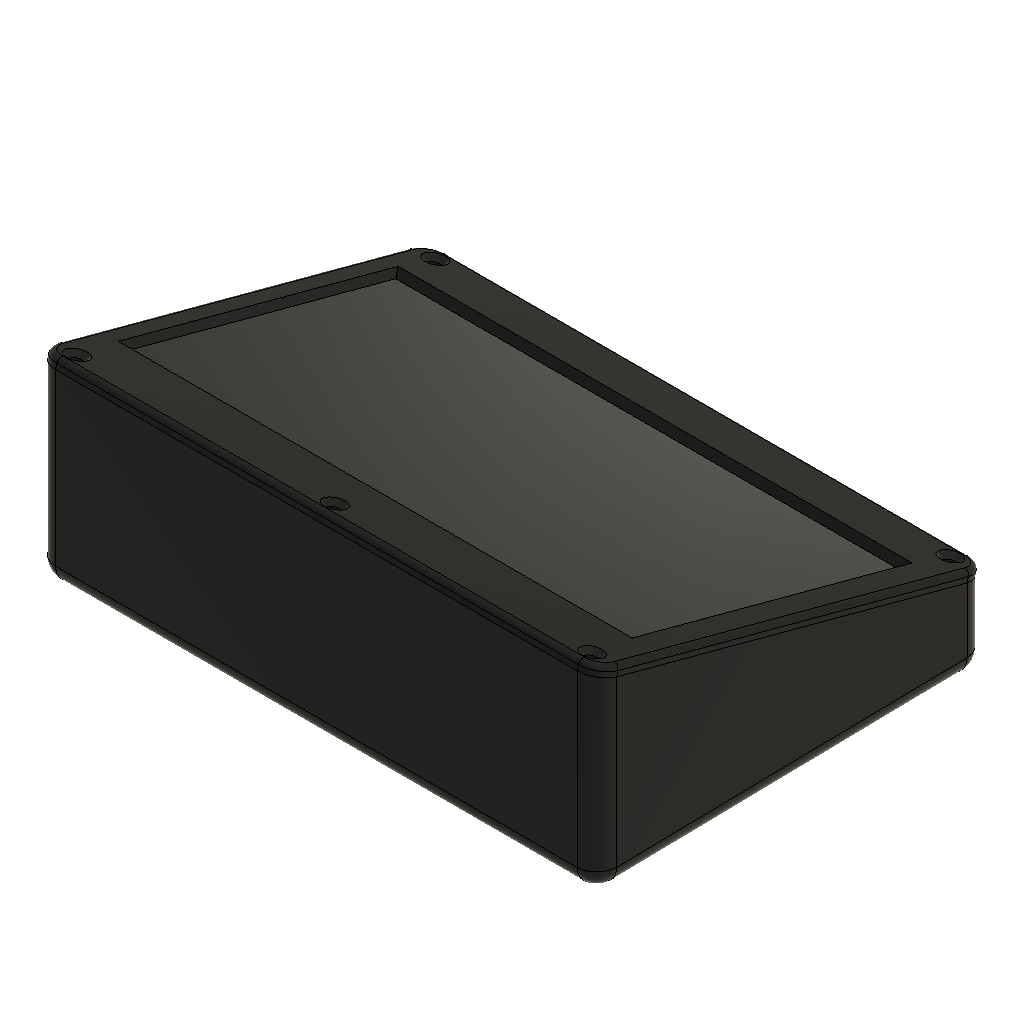
RadioCaseShort (Autodesk Fusion 360 design; units mm, degrees)
part number: 2026-10-21-15-02-30-773
Autodesk Fusion 360 part; units mm, degrees
sketch "Sketch1" plane through (0, 0, 0) normal (1, 0, 0) x (0, 0, -1)
  line L0 (0, 0) -> (0, 123)
  line L1 (0, 123) -> (23.1822, 129.2117)
  line L2 (23.1822, 129.2117) -> (56.0237, 15.0115)
  line L3 (56.0237, 15.0115) -> (0, 0)
extrude "Extrude1" add sketch "Sketch1" along normal blind 171 makes body 1
fillet "Fillet1" radius 6 8 edges at (0, 7.5058, -28.0118) (85.5, 15.0115, -56.0237) (171, 7.5058, -28.0118) (0, 126.1058, -11.5911) (171, 126.1058, -11.5911) (85.5, 129.2117, -23.1822) (0, 72.1116, -39.603) (171, 72.1116, -39.603) on bodies 1
extrude "Extrude2" add 1 faces at (59, 41, 0) along direction (0, 0, 1) blind 3 separate body on bodies 1 makes body 2
ref_plane "WorkPlane1" through (0, 0, -61.0237) normal (0, 0, 1) x (1, 0, 0)
sketch "Sketch2" plane through (0, 0, -61.0237) normal (0, 0, 1) x (1, 0, 0)
  circle A0 centre (40.5, 36) radius 4.5
extrude "Extrude3" add sketch "Sketch2" along normal blind 44.7237 separate body makes body 3
ref_plane "WorkPlane2" through (0, 0, -16.3) normal (0, 0, 1) x (1, 0, 0)
sketch "Sketch3" plane through (0, 0, -16.3) normal (0, 0, 1) x (1, 0, 0)
  circle A0 centre (40.5, 36) radius 3.5
extrude "Extrude4" add sketch "Sketch3" along normal blind 6 bodies 3
ref_plane "WorkPlane3" through (0, 0, -61.0237) normal (0, 0, 1) x (1, 0, 0)
sketch "Sketch4" plane through (0, 0, -61.0237) normal (0, 0, 1) x (1, 0, 0)
  circle A0 centre (40.5, 88) radius 4.5
extrude "Extrude5" add sketch "Sketch4" along normal blind 44.7237 separate body makes body 4
ref_plane "WorkPlane4" through (0, 0, -16.3) normal (0, 0, 1) x (1, 0, 0)
sketch "Sketch5" plane through (0, 0, -16.3) normal (0, 0, 1) x (1, 0, 0)
  circle A0 centre (40.5, 88) radius 3.5
extrude "Extrude6" add sketch "Sketch5" along normal blind 6 bodies 4
ref_plane "WorkPlane5" through (0, 0, -61.0237) normal (0, 0, 1) x (1, 0, 0)
sketch "Sketch6" plane through (0, 0, -61.0237) normal (0, 0, 1) x (1, 0, 0)
  circle A0 centre (130.5, 36) radius 4.5
extrude "Extrude7" add sketch "Sketch6" along normal blind 44.7237 separate body makes body 5
ref_plane "WorkPlane6" through (0, 0, -16.3) normal (0, 0, 1) x (1, 0, 0)
sketch "Sketch7" plane through (0, 0, -16.3) normal (0, 0, 1) x (1, 0, 0)
  circle A0 centre (130.5, 36) radius 3.5
extrude "Extrude8" add sketch "Sketch7" along normal blind 6 bodies 5
ref_plane "WorkPlane7" through (0, 0, -61.0237) normal (0, 0, 1) x (1, 0, 0)
sketch "Sketch8" plane through (0, 0, -61.0237) normal (0, 0, 1) x (1, 0, 0)
  circle A0 centre (130.5, 88) radius 4.5
extrude "Extrude9" add sketch "Sketch8" along normal blind 44.7237 separate body makes body 6
ref_plane "WorkPlane8" through (0, 0, -16.3) normal (0, 0, 1) x (1, 0, 0)
sketch "Sketch9" plane through (0, 0, -16.3) normal (0, 0, 1) x (1, 0, 0)
  circle A0 centre (130.5, 88) radius 3.5
extrude "Extrude10" add sketch "Sketch9" along normal blind 6 bodies 6
ref_plane "WorkPlane9" through (0, 0, -61.0237) normal (0, 0, 1) x (1, 0, 0)
sketch "Sketch10" plane through (0, 0, -61.0237) normal (0, 0, 1) x (1, 0, 0)
  circle A0 centre (7, 5) radius 3.5
extrude "Extrude11" add sketch "Sketch10" along normal blind 61.0237 separate body makes body 7
ref_plane "WorkPlane10" through (0, 0, -61.0237) normal (0, 0, 1) x (1, 0, 0)
sketch "Sketch11" plane through (0, 0, -61.0237) normal (0, 0, 1) x (1, 0, 0)
  circle A0 centre (85.5, 5) radius 3.5
extrude "Extrude12" add sketch "Sketch11" along normal blind 61.0237 separate body makes body 8
ref_plane "WorkPlane11" through (0, 0, -61.0237) normal (0, 0, 1) x (1, 0, 0)
sketch "Sketch12" plane through (0, 0, -61.0237) normal (0, 0, 1) x (1, 0, 0)
  circle A0 centre (164, 5) radius 3.5
extrude "Extrude13" add sketch "Sketch12" along normal blind 61.0237 separate body makes body 9
ref_plane "WorkPlane12" through (0, 0, -61.0237) normal (0, 0, 1) x (1, 0, 0)
sketch "Sketch13" plane through (0, 0, -61.0237) normal (0, 0, 1) x (1, 0, 0)
  circle A0 centre (7, 118) radius 3.5
extrude "Extrude14" add sketch "Sketch13" along normal blind 61.0237 separate body makes body 10
ref_plane "WorkPlane13" through (0, 0, -61.0237) normal (0, 0, 1) x (1, 0, 0)
sketch "Sketch14" plane through (0, 0, -61.0237) normal (0, 0, 1) x (1, 0, 0)
  circle A0 centre (164, 118) radius 3.5
extrude "Extrude15" add sketch "Sketch14" along normal blind 61.0237 separate body makes body 11
combine "Combine1" operation intersect target body 3 tool bodies 1 keep tools
combine "Combine2" operation intersect target body 4 tool bodies 1 keep tools
combine "Combine3" operation intersect target body 5 tool bodies 1 keep tools
combine "Combine4" operation intersect target body 6 tool bodies 1 keep tools
combine "Combine5" operation intersect target body 7 tool bodies 1 keep tools
combine "Combine6" operation intersect target body 8 tool bodies 1 keep tools
combine "Combine7" operation intersect target body 9 tool bodies 1 keep tools
combine "Combine8" operation intersect target body 10 tool bodies 1 keep tools
combine "Combine9" operation intersect target body 11 tool bodies 1 keep tools
shell "Shell1" thickness 2.5 removed faces 1 at (59, 41, 0) on bodies 1
combine "Combine10" operation add target body 1 tool bodies 3 4 5 6 7 8 9 10 11
ref_plane "WorkPlane14" through (0, 0, -66.0237) normal (0, 0, 1) x (1, 0, 0)
sketch "Sketch15" plane through (0, 0, -66.0237) normal (0, 0, 1) x (1, 0, 0)
  circle A0 centre (40.5, 36) radius 2.75
extrude "Extrude16" cut sketch "Sketch15" along normal blind 49.7237 bodies 1
ref_plane "WorkPlane15" through (0, 0, -16.8) normal (0, 0, 1) x (1, 0, 0)
sketch "Sketch16" plane through (0, 0, -16.8) normal (0, 0, 1) x (1, 0, 0)
  circle A0 centre (40.5, 36) radius 1.2
extrude "Extrude17" cut sketch "Sketch16" along normal blind 7 bodies 1
ref_plane "WorkPlane16" through (0, 0, -66.0237) normal (0, 0, 1) x (1, 0, 0)
sketch "Sketch17" plane through (0, 0, -66.0237) normal (0, 0, 1) x (1, 0, 0)
  circle A0 centre (40.5, 88) radius 2.75
extrude "Extrude18" cut sketch "Sketch17" along normal blind 49.7237 bodies 1
ref_plane "WorkPlane17" through (0, 0, -16.8) normal (0, 0, 1) x (1, 0, 0)
sketch "Sketch18" plane through (0, 0, -16.8) normal (0, 0, 1) x (1, 0, 0)
  circle A0 centre (40.5, 88) radius 1.2
extrude "Extrude19" cut sketch "Sketch18" along normal blind 7 bodies 1
ref_plane "WorkPlane18" through (0, 0, -66.0237) normal (0, 0, 1) x (1, 0, 0)
sketch "Sketch19" plane through (0, 0, -66.0237) normal (0, 0, 1) x (1, 0, 0)
  circle A0 centre (130.5, 36) radius 2.75
extrude "Extrude20" cut sketch "Sketch19" along normal blind 49.7237 bodies 1
ref_plane "WorkPlane19" through (0, 0, -16.8) normal (0, 0, 1) x (1, 0, 0)
sketch "Sketch20" plane through (0, 0, -16.8) normal (0, 0, 1) x (1, 0, 0)
  circle A0 centre (130.5, 36) radius 1.2
extrude "Extrude21" cut sketch "Sketch20" along normal blind 7 bodies 1
ref_plane "WorkPlane20" through (0, 0, -66.0237) normal (0, 0, 1) x (1, 0, 0)
sketch "Sketch21" plane through (0, 0, -66.0237) normal (0, 0, 1) x (1, 0, 0)
  circle A0 centre (130.5, 88) radius 2.75
extrude "Extrude22" cut sketch "Sketch21" along normal blind 49.7237 bodies 1
ref_plane "WorkPlane21" through (0, 0, -16.8) normal (0, 0, 1) x (1, 0, 0)
sketch "Sketch22" plane through (0, 0, -16.8) normal (0, 0, 1) x (1, 0, 0)
  circle A0 centre (130.5, 88) radius 1.2
extrude "Extrude23" cut sketch "Sketch22" along normal blind 7 bodies 1
ref_plane "WorkPlane22" through (0, 0, -12) normal (0, 0, 1) x (1, 0, 0)
sketch "Sketch23" plane through (0, 0, -12) normal (0, 0, 1) x (1, 0, 0)
  circle A0 centre (7, 5) radius 1.25
extrude "Extrude24" cut sketch "Sketch23" along normal blind 12.5 bodies 1
ref_plane "WorkPlane23" through (0, 0, -12) normal (0, 0, 1) x (1, 0, 0)
sketch "Sketch24" plane through (0, 0, -12) normal (0, 0, 1) x (1, 0, 0)
  circle A0 centre (85.5, 5) radius 1.25
extrude "Extrude25" cut sketch "Sketch24" along normal blind 12.5 bodies 1
ref_plane "WorkPlane24" through (0, 0, -12) normal (0, 0, 1) x (1, 0, 0)
sketch "Sketch25" plane through (0, 0, -12) normal (0, 0, 1) x (1, 0, 0)
  circle A0 centre (164, 5) radius 1.25
extrude "Extrude26" cut sketch "Sketch25" along normal blind 12.5 bodies 1
ref_plane "WorkPlane25" through (0, 0, -12) normal (0, 0, 1) x (1, 0, 0)
sketch "Sketch26" plane through (0, 0, -12) normal (0, 0, 1) x (1, 0, 0)
  circle A0 centre (7, 118) radius 1.25
extrude "Extrude27" cut sketch "Sketch26" along normal blind 12.5 bodies 1
ref_plane "WorkPlane26" through (0, 0, -12) normal (0, 0, 1) x (1, 0, 0)
sketch "Sketch27" plane through (0, 0, -12) normal (0, 0, 1) x (1, 0, 0)
  circle A0 centre (164, 118) radius 1.25
extrude "Extrude28" cut sketch "Sketch27" along normal blind 12.5 bodies 1
ref_plane "WorkPlane27" through (-1, 0, 0) normal (1, 0, 0) x (0, 1, 0)
sketch "Sketch28" plane through (-1, 0, 0) normal (1, 0, 0) x (0, 0, -1)
  line L0 (12.9, 42) -> (12.9, 90)
  line L1 (4.9, 42) -> (4.9, 90)
  arc A0 (12.9, 90) -> (4.9, 90) centre (8.9, 90) ccw
  arc A1 (4.9, 42) -> (12.9, 42) centre (8.9, 42) ccw
extrude "Extrude29" cut sketch "Sketch28" along normal blind 4.1 bodies 1
ref_plane "WorkPlane28" through (0, 0, -10.2) normal (0, 0, 1) x (1, 0, 0)
sketch "Sketch29" plane through (0, 0, -10.2) normal (0, 0, 1) x (1, 0, 0)
  line L0 (56.3, 112) -> (72.7, 112)
  line L1 (72.7, 112) -> (72.7, 143)
  line L2 (72.7, 143) -> (56.3, 143)
  line L3 (56.3, 143) -> (56.3, 112)
extrude "Extrude30" cut sketch "Sketch29" along normal blind 4 bodies 1
ref_plane "WorkPlane29" through (0, 0, -13) normal (0, 0, 1) x (1, 0, 0)
sketch "Sketch30" plane through (0, 0, -13) normal (0, 0, 1) x (1, 0, 0)
  line L0 (54.5, 124.5) -> (54.5, 133)
  line L1 (74.5, 124.5) -> (74.5, 133)
  arc A0 (74.5, 133) -> (54.5, 133) centre (64.5, 133) ccw
  arc A1 (54.5, 124.5) -> (74.5, 124.5) centre (64.5, 124.5) ccw
extrude "Extrude31" cut sketch "Sketch30" along normal blind 13.1 bodies 1
sketch "Sketch31" plane through (0, 16.0272, -55.7316) normal (0, 0.276377, -0.961049) x (0, 0.961049, 0.276377)
  ellipse E0 centre (74.8898, 130.5) end of major axis (77.7513, 130.5) minor radius 2.75
  ellipse E1 centre (20.7823, 130.5) end of major axis (23.6437, 130.5) minor radius 2.75
  ellipse E2 centre (74.8898, 40.5) end of major axis (77.7513, 40.5) minor radius 2.75
  ellipse E3 centre (20.7823, 40.5) end of major axis (23.6437, 40.5) minor radius 2.75
  line L0 (111.8801, 165) -> (5.0535, 165)
  line L1 (5.0535, 165) -> (5.0535, 6)
  line L2 (5.0535, 6) -> (111.8801, 6)
  line L3 (111.8801, 6) -> (111.8801, 165)
  circle A0 centre (53.1613, 82.5) radius 1
  circle A1 centre (53.1613, 85.5) radius 1
  circle A2 centre (53.1613, 88.5) radius 1
  circle A3 centre (55.7594, 81) radius 1
  circle A4 centre (55.7594, 84) radius 1
  circle A5 centre (55.7594, 87) radius 1
  circle A6 centre (55.7594, 90) radius 1
  circle A7 centre (58.3574, 79.5) radius 1
  circle A8 centre (58.3574, 82.5) radius 1
  circle A9 centre (58.3574, 85.5) radius 1
  circle A10 centre (58.3574, 88.5) radius 1
  circle A11 centre (58.3574, 91.5) radius 1
  circle A12 centre (60.9555, 81) radius 1
  circle A13 centre (60.9555, 84) radius 1
  circle A14 centre (60.9555, 87) radius 1
  circle A15 centre (60.9555, 90) radius 1
  circle A16 centre (63.5536, 82.5) radius 1
  circle A17 centre (63.5536, 85.5) radius 1
  circle A18 centre (63.5536, 88.5) radius 1
extrude "Extrude32" cut sketch "Sketch31" against normal blind 3.5 contours A0 | A1 | A2 | A3 | A4 | A5 | A6 | A7 | A8 | A9 | A10 | A11 | A12 | A13 | A14 | A15 | A16 | A17 | A18 bodies 1
ref_plane "WorkPlane30" through (85.5, 71.5257, -37.1701) normal (0, 0.276377, -0.961049) x (0, 0.961049, 0.276377)
sketch "Sketch32" plane through (0, 15.3363, -53.329) normal (0, 0.276377, -0.961049) x (0, 0.961049, 0.276377)
  circle A0 centre (58.3574, 85.5) radius 11.9
  circle A1 centre (58.3574, 85.5) radius 10.3
extrude "Extrude33" add sketch "Sketch32" against normal blind 5.6 bodies 1
fillet "Fillet2" radius 1.5 64 edges at (1.7574, 1.8194, 3) (85.5, 0, 3) (169.2426, 1.8194, 3) (171, 61.5, 3) (169.2426, 121.1806, 3) (85.5, 123, 3) (1.7574, 121.1806, 3) (0, 61.5, 3) (85.5, 0, 3) (169.2426, 1.8194, 3) (171, 61.5, 3) (169.2426, 121.1806, 3) (85.5, 123, 3) (1.7574, 121.1806, 3) (0, 61.5, 3) (1.7574, 1.8194, 3) (169.2426, 1.8194, 3) (171, 61.5, 3) (169.2426, 121.1806, 3) (85.5, 123, 3) (1.7574, 121.1806, 3) (0, 61.5, 3) (1.7574, 1.8194, 3) (85.5, 0, 3) (171, 61.5, 3) (169.2426, 121.1806, 3) (85.5, 123, 3) (1.7574, 121.1806, 3) (0, 61.5, 3) (1.7574, 1.8194, 3) (85.5, 0, 3) (169.2426, 1.8194, 3) (169.2426, 121.1806, 3) (85.5, 123, 3) (1.7574, 121.1806, 3) (0, 61.5, 3) (1.7574, 1.8194, 3) (85.5, 0, 3) (169.2426, 1.8194, 3) (171, 61.5, 3) (85.5, 123, 3) (1.7574, 121.1806, 3) (0, 61.5, 3) (1.7574, 1.8194, 3) (85.5, 0, 3) (169.2426, 1.8194, 3) (171, 61.5, 3) (169.2426, 121.1806, 3) (1.7574, 121.1806, 3) (0, 61.5, 3) (1.7574, 1.8194, 3) (85.5, 0, 3) (169.2426, 1.8194, 3) (171, 61.5, 3) (169.2426, 121.1806, 3) (85.5, 123, 3) (0, 61.5, 3) (1.7574, 1.8194, 3) (85.5, 0, 3) (169.2426, 1.8194, 3) (171, 61.5, 3) (169.2426, 121.1806, 3) (85.5, 123, 3) (1.7574, 121.1806, 3) on bodies 2
ref_plane "WorkPlane31" through (0, 0, -1) normal (0, 0, 1) x (1, 0, 0)
sketch "Sketch33" plane through (0, 0, -1) normal (0, 0, 1) x (1, 0, 0)
  line L0 (6.1, 18.9) -> (162.71, 18.9)
  line L1 (162.71, 18.9) -> (162.71, 107.22)
  line L2 (162.71, 107.22) -> (6.1, 107.22)
  line L3 (6.1, 107.22) -> (6.1, 18.9)
extrude "Extrude34" cut sketch "Sketch33" along normal blind 5 bodies 2
ref_plane "WorkPlane32" through (0, 0, -1) normal (0, 0, 1) x (1, 0, 0)
sketch "Sketch34" plane through (0, 0, -1) normal (0, 0, 1) x (1, 0, 0)
  circle A0 centre (7, 5) radius 1.7
extrude "Extrude35" cut sketch "Sketch34" along normal blind 5 bodies 2
ref_plane "WorkPlane33" through (0, 0, 3) normal (0, 0, 1) x (1, 0, 0)
sketch "Sketch35" plane through (0, 0, 3) normal (0, 0, 1) x (1, 0, 0)
  circle A0 centre (7, 5) radius 3.2
extrude "Extrude36" cut sketch "Sketch35" against normal blind 1.5 draft -45 bodies 2
ref_plane "WorkPlane34" through (0, 0, -1) normal (0, 0, 1) x (1, 0, 0)
sketch "Sketch36" plane through (0, 0, -1) normal (0, 0, 1) x (1, 0, 0)
  circle A0 centre (85.5, 5) radius 1.7
extrude "Extrude37" cut sketch "Sketch36" along normal blind 5 bodies 2
ref_plane "WorkPlane35" through (0, 0, 3) normal (0, 0, 1) x (1, 0, 0)
sketch "Sketch37" plane through (0, 0, 3) normal (0, 0, 1) x (1, 0, 0)
  circle A0 centre (85.5, 5) radius 3.2
extrude "Extrude38" cut sketch "Sketch37" against normal blind 1.5 draft -45 bodies 2
ref_plane "WorkPlane36" through (0, 0, -1) normal (0, 0, 1) x (1, 0, 0)
sketch "Sketch38" plane through (0, 0, -1) normal (0, 0, 1) x (1, 0, 0)
  circle A0 centre (164, 5) radius 1.7
extrude "Extrude39" cut sketch "Sketch38" along normal blind 5 bodies 2
ref_plane "WorkPlane37" through (0, 0, 3) normal (0, 0, 1) x (1, 0, 0)
sketch "Sketch39" plane through (0, 0, 3) normal (0, 0, 1) x (1, 0, 0)
  circle A0 centre (164, 5) radius 3.2
extrude "Extrude40" cut sketch "Sketch39" against normal blind 1.5 draft -45 bodies 2
ref_plane "WorkPlane38" through (0, 0, -1) normal (0, 0, 1) x (1, 0, 0)
sketch "Sketch40" plane through (0, 0, -1) normal (0, 0, 1) x (1, 0, 0)
  circle A0 centre (7, 118) radius 1.7
extrude "Extrude41" cut sketch "Sketch40" along normal blind 5 bodies 2
ref_plane "WorkPlane39" through (0, 0, 3) normal (0, 0, 1) x (1, 0, 0)
sketch "Sketch41" plane through (0, 0, 3) normal (0, 0, 1) x (1, 0, 0)
  circle A0 centre (7, 118) radius 3.2
extrude "Extrude42" cut sketch "Sketch41" against normal blind 1.5 draft -45 bodies 2
ref_plane "WorkPlane40" through (0, 0, -1) normal (0, 0, 1) x (1, 0, 0)
sketch "Sketch42" plane through (0, 0, -1) normal (0, 0, 1) x (1, 0, 0)
  circle A0 centre (164, 118) radius 1.7
extrude "Extrude43" cut sketch "Sketch42" along normal blind 5 bodies 2
ref_plane "WorkPlane41" through (0, 0, 3) normal (0, 0, 1) x (1, 0, 0)
sketch "Sketch43" plane through (0, 0, 3) normal (0, 0, 1) x (1, 0, 0)
  circle A0 centre (164, 118) radius 3.2
extrude "Extrude44" cut sketch "Sketch43" against normal blind 1.5 draft -45 bodies 2
ref_plane "WorkPlane42" through (85.5, 71.5257, -37.1701) normal (0, 0.276377, -0.961049) x (0, 0.961049, 0.276377)
sketch "Sketch44" plane through (0, 15.3363, -53.329) normal (0, 0.276377, -0.961049) x (0, 0.961049, 0.276377)
  circle A0 centre (58.3574, 85.5) radius 10
extrude "Extrude45" add sketch "Sketch44" against normal blind 5 separate body makes body 12
ref_plane "WorkPlane43" through (0, 0, -5.7) normal (0, 0, 1) x (1, 0, 0)
sketch "Sketch45" plane through (0, 0, -5.7) normal (0, 0, 1) x (1, 0, 0)
  line L0 (3, 11.85) -> (168, 11.85)
  line L1 (168, 11.85) -> (168, 112.15)
  line L2 (168, 112.15) -> (3, 112.15)
  line L3 (3, 112.15) -> (3, 11.85)
extrude "Extrude46" add sketch "Sketch45" along normal blind 5.4 separate body makes body 13
ref_plane "WorkPlane44" through (0, 0, -7.3) normal (0, 0, 1) x (1, 0, 0)
sketch "Sketch46" plane through (0, 0, -7.3) normal (0, 0, 1) x (1, 0, 0)
  line L0 (3, 10) -> (168, 10)
  line L1 (168, 10) -> (168, 114)
  line L2 (168, 114) -> (3, 114)
  line L3 (3, 114) -> (3, 10)
extrude "Extrude47" add sketch "Sketch46" along normal blind 1.6 separate body makes body 14
ref_plane "WorkPlane45" through (0, 0, -10.3) normal (0, 0, 1) x (1, 0, 0)
sketch "Sketch47" plane through (0, 0, -10.3) normal (0, 0, 1) x (1, 0, 0)
  circle A0 centre (40.5, 36) radius 1.75
extrude "Extrude48" add sketch "Sketch47" along normal blind 3 separate body makes body 15
ref_plane "WorkPlane46" through (0, 0, -10.3) normal (0, 0, 1) x (1, 0, 0)
sketch "Sketch48" plane through (0, 0, -10.3) normal (0, 0, 1) x (1, 0, 0)
  circle A0 centre (40.5, 88) radius 1.75
extrude "Extrude49" add sketch "Sketch48" along normal blind 3 separate body makes body 16
ref_plane "WorkPlane47" through (0, 0, -10.3) normal (0, 0, 1) x (1, 0, 0)
sketch "Sketch49" plane through (0, 0, -10.3) normal (0, 0, 1) x (1, 0, 0)
  circle A0 centre (130.5, 36) radius 1.75
extrude "Extrude50" add sketch "Sketch49" along normal blind 3 separate body makes body 17
ref_plane "WorkPlane48" through (0, 0, -10.3) normal (0, 0, 1) x (1, 0, 0)
sketch "Sketch50" plane through (0, 0, -10.3) normal (0, 0, 1) x (1, 0, 0)
  circle A0 centre (130.5, 88) radius 1.75
extrude "Extrude51" add sketch "Sketch50" along normal blind 3 separate body makes body 18
move_body "Move1" bodies 1 2 12 13 14 15 16 17 18 to x (1, 0, 0) y (0, 0.965926, -0.258819) z (0, 0.258819, 0.965926) at (0, 0, 0)
equation "d124 = -( 3.50 mm )"
equation "d128 = -( 5.60 mm )"
equation "d142 = -( 1.50 mm )"
equation "d150 = -( 1.50 mm )"
equation "d158 = -( 1.50 mm )"
equation "d166 = -( 1.50 mm )"
equation "d174 = -( 1.50 mm )"
equation "d178 = -( 5.00 mm )"
named bodies: "Body", "FrontPanel", "Speaker_REF", "Glass", "PCB", "Standoff_REF", "Standoff_REF (1)", "Standoff_REF (2)", "Standoff_REF (3)"
